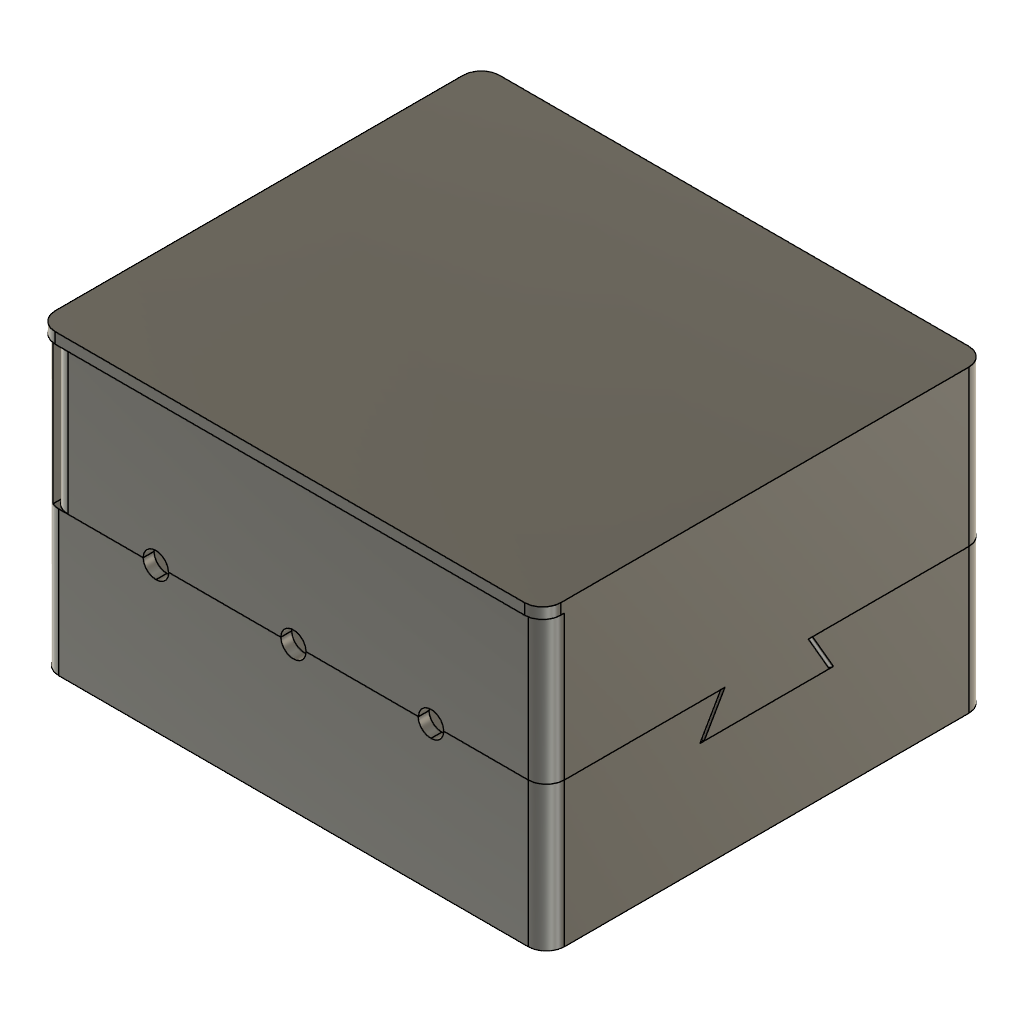
Box (Autodesk Fusion 360 design; units mm, degrees)
part number: 2026-10-24-19-44-33-604
Autodesk Fusion 360 part; units mm, degrees
sketch "Sketch1" plane through (0, 0, 0) normal (0, 0, 1) x (1, 0, 0)
  line L0 (-45, 0) -> (40, 0)
  line L1 (40, 0) -> (40, 122)
  line L2 (-45, 0) -> (-45, 122)
  line L3 (-45, 122) -> (40, 122)
  dimension "d1" = 85
  dimension "d2" = 122
  dimension "d3" = 122
  constraint horizontal L0
  constraint perpendicular L0 L1
  constraint perpendicular L0 L2
  measures "d1" distance of L0.start L0.end
  measures "d2" distance of L0.end L1.end
  measures "d3" distance of L0.start L2.end
extrude "Extrude1" add sketch "Sketch1" along normal blind 10 makes body 1
sketch "Sketch2" plane through (-45, 0, 0) normal (1, 0, 0) x (0, 1, 0)
  line L0 (122, 10) -> (0, 10)
  line L1 (74.4268, 10) -> (74.4268, 21)
  line L2 (74.4268, 21) -> (65.4268, 21)
  line L3 (65.4268, 21) -> (65.4268, 10)
  line L4 (55, 10) -> (41.8, 10)
  line L5 (55, 10) -> (55, 29)
  line L6 (55, 29) -> (41.8, 29)
  line L7 (41.8, 29) -> (41.8, 10)
  line L8 (122, 29) -> (122, 10)
  line L9 (0, 29) -> (0, 10)
  line L10 (122, 29) -> (122, 32)
  line L11 (122, 32) -> (0, 32)
  line L12 (0, 32) -> (0, 29)
  line L13 (122, 0) -> (0, 0)
  line L14 (0, 0) -> (0, 10)
  line L15 (0, 10) -> (122, 10)
  line L16 (122, 10) -> (122, 0)
  dimension "d6" = 11
  dimension "d7" = 9
  dimension "d8" = 13.2
  dimension "d9" = 19
  dimension "d10" = 13.2
  dimension "d11" = 3
  constraint coincident L0 L1.start
  constraint perpendicular L1 L2
  constraint perpendicular L2 L3
  constraint coincident L0 L4.start
  constraint perpendicular L4 L5
  constraint perpendicular L5 L6
  constraint coincident L0.start L8.end
  constraint perpendicular L0 L8
  constraint coincident L0.end L9.end
  constraint perpendicular L0 L9
  constraint perpendicular L10 L11
  measures "d6" distance of L1.start L1.end
  measures "d7" distance of L1.end L2.end
  measures "d8" distance of L4.start L4.end
  measures "d9" distance of L4.start L5.end
  measures "d10" distance of L5.end L6.end
  measures "d11" distance of L8.start L10.end
extrude "Extrude2" add sketch "Sketch2" along normal blind 3 contours L0 L1 L2 L3 L5 L6 L7 L8 L9 L10 L11 L12 L15 bodies 1
sketch "Sketch5" plane through (0, 0, 0) normal (0, 1, 0) x (1, 0, 0)
  line L0 (-35, -16) -> (-45, -16)
  line L1 (-45, -16) -> (40, -16)
  line L2 (40, -16) -> (40, -10)
  line L3 (40, -10) -> (-41.9493, -10)
  line L4 (-41.9493, -10) -> (-45, -10)
  line L5 (-45, -10) -> (-45, -16)
  constraint perpendicular L1 L2
  constraint parallel L3 L4
  constraint perpendicular L1 L5
extrude "Extrude3" add sketch "Sketch5" along normal blind 41.8 bodies 1
extrude "Extrude4" add 1 faces at (40, 13.9333, 8.6667) along direction (1, 0, 0) blind 55 on bodies 1 bodies 1
sketch "Sketch8" plane through (-45, 0, 0) normal (-1, 0, 0) x (0, -1, 0)
  line L0 (-41.8, 10) -> (-55, 10)
  line L1 (-55, 10) -> (-55, 29)
  line L2 (-55, 29) -> (-41.8, 29)
  line L3 (-41.8, 29) -> (-41.8, 10)
  line L4 (0, 0) -> (0, 32)
  line L5 (0, 32) -> (-122, 32)
  line L6 (-122, 32) -> (-122, 0)
  line L7 (-122, 0) -> (0, 0)
  line L8 (-74.4268, 10) -> (-74.4268, 21)
  line L9 (-74.4268, 21) -> (-65.4268, 21)
  line L10 (-65.4268, 21) -> (-65.4268, 10)
  line L11 (-65.4268, 10) -> (-74.4268, 10)
  line L12 (0, 0) -> (0, 80)
  line L13 (0, 0) -> (-122, 0)
  line L14 (-122, 0) -> (-122, 80)
  line L15 (-122, 80) -> (0, 80)
  dimension "d24" = 80
  constraint coincident L4.start L7.end
  constraint perpendicular L7 L12
  constraint coincident L6.end L7.start
  constraint perpendicular L5 L14
  constraint perpendicular L12 L15
  measures "d24" distance of L4.start L12.end
extrude "Extrude5" add sketch "Sketch8" against normal blind 3 contours L5 L12 L14 L15 bodies 1
move_body "Move1" bodies 1 to x (1, 0, 0) y (0, 1, 0) z (0, 0, 1) at (-25, 0, 0)
sketch "Sketch12" plane through (0, 0, 0) normal (0, 1, 0) x (1, 0, 0)
  line L0 (70, 0) -> (70, -40)
  line L1 (70, -40) -> (-70, -40)
  line L2 (-70, -40) -> (-70, 0)
  line L3 (-70, 0) -> (70, 0)
  dimension "d29" = 40
  constraint vertical L0
  constraint perpendicular L0 L1
  constraint perpendicular L1 L2
  constraint perpendicular L0 L3
  measures "d29" distance of L0.start L0.end
extrude "Extrude6" add sketch "Sketch12" along normal blind 41.8 bodies 1
sketch "Sketch13" plane through (0, 0, 0) normal (0, 1, 0) x (1, 0, 0)
  circle A0 centre (0, -40) radius 3.5
  circle A1 centre (-35, -40) radius 3.5
  circle A2 centre (35, -40) radius 3.5
  dimension "d32" = 7
  dimension "d33" = 35
  dimension "d34" = 7
  measures "d32" diameter of A0
  measures "d33" distance of A0.centre A1.centre
  measures "d34" diameter of A1
extrude "Extrude7" cut sketch "Sketch13" along normal blind 45 bodies 1
sketch "Sketch14" plane through (0, 0, 40) normal (0, 0, 1) x (-1, 0, 0)
  line L0 (-31.5, 0) -> (-31.5, -41.8)
  line L1 (-31.5, -41.8) -> (-3.5, -41.8)
  line L2 (-3.5, 0) -> (-31.5, 0)
  line L3 (-3.5, -3) -> (-17.6, -3)
  line L4 (3.5, -3) -> (17.6, -3)
  line L5 (17.6, -3) -> (17.6, -35.2)
  line L6 (-17.6, -35.2) -> (-17.6, -3)
  line L7 (3.5, -3) -> (-3.5, -3)
  line L8 (17.6, -35.2) -> (17.6, -42)
  line L9 (-17.6, -35.2) -> (-17.6, -42)
  line L10 (-17.6, -42) -> (17.6, -42)
  dimension "d39" = 14.1
  dimension "d40" = 14.1
  dimension "d41" = 32.2
  dimension "d42" = 35.2
  constraint horizontal L3
  constraint perpendicular L4 L5
  constraint parallel L3 L7
  constraint parallel L5 L8
  constraint vertical L9
  constraint perpendicular L8 L10
  measures "d39" distance of L3.start L3.end
  measures "d40" distance of L4.start L4.end
  measures "d41" distance of L4.end L5.end
  measures "d42" distance of L5.end L6.start
extrude "Extrude8" cut sketch "Sketch14" against normal blind 8.2 bodies 1
sketch "Sketch15" plane through (0, 0, 0) normal (0, -1, 0) x (1, 0, 0)
  arc A0 (31.5, 40) -> (38.5, 40) centre (35, 40) ccw
  line L0 (31.5, 40) -> (3.5, 40)
  arc A1 (-3.5, 40) -> (3.5, 40) centre (0, 40) ccw
  line L1 (-3.5, 40) -> (-31.5, 40)
  arc A2 (-38.5, 40) -> (-31.5, 40) centre (-35, 40) ccw
  line L2 (-38.5, 40) -> (-67, 40)
  line L3 (-67, 40) -> (-67, 80)
  line L4 (-67, 80) -> (-70, 80)
  line L5 (-70, 80) -> (-70, 0)
  line L6 (-70, 0) -> (70, 0)
  line L7 (70, 0) -> (70, 40)
  line L8 (70, 40) -> (38.5, 40)
  line L9 (-38.5, 40) -> (-31.5, 40)
  line L10 (31.5, 40) -> (38.5, 40)
  constraint coincident A2.start L2.start
  constraint coincident L1.end A2.end
  constraint coincident A0.start L0.start
  constraint coincident A0.end L8.end
extrude "Extrude9" add sketch "Sketch15" against normal blind 41.8 contours A0 L10 | A2 L9 bodies 1
sketch "Sketch16" plane through (0, 0, 0) normal (0, -1, 0) x (1, 0, 0)
sketch "Sketch17" plane through (0, 0, 40) normal (0, 0, 1) x (-1, 0, 0)
  line L0 (17.6, -41.8) -> (67, -41.8)
  line L1 (67, -41.8) -> (67, 0)
  line L2 (67, 0) -> (3.5, 0)
  line L3 (3.5, 0) -> (3.5, -3)
  line L4 (3.5, -3) -> (17.6, -3)
  line L5 (17.6, -3) -> (17.6, -41.8)
  line L6 (3.5, -3) -> (17.6, -3)
  line L7 (17.6, -35.2) -> (17.6, -42)
  line L8 (-31.5, -41.8) -> (-3.5, -41.8)
  line L9 (17.6, -3) -> (17.6, -35.2)
  line L10 (-3.5, 0) -> (-31.5, 0)
  line L11 (-17.6, -42) -> (17.6, -42)
  line L12 (-3.5, -3) -> (-17.6, -3)
  line L13 (-17.6, -35.2) -> (-17.6, -42)
  line L14 (3.5, -3) -> (-3.5, -3)
  line L15 (-17.6, -35.2) -> (-17.6, -3)
  line L16 (41.5, -3) -> (55.6, -3)
  line L17 (55.6, -35.2) -> (55.6, -42)
  line L18 (6.5, -41.8) -> (34.5, -41.8)
  line L19 (55.6, -3) -> (55.6, -35.2)
  line L20 (20.4, -42) -> (55.6, -42)
  line L21 (34.5, -3) -> (20.4, -3)
  line L22 (20.4, -35.2) -> (20.4, -42)
  line L23 (41.5, -3) -> (34.5, -3)
  line L24 (20.4, -35.2) -> (20.4, -3)
  line L25 (-41.5, -3) -> (-34.5, -3)
  line L26 (-34.5, -3) -> (-20.4, -3)
  line L27 (-55.6, -3) -> (-55.6, -35.2)
  line L28 (-41.5, -3) -> (-55.6, -3)
  line L29 (-55.6, -35.2) -> (-55.6, -42)
  line L30 (-20.4, -35.2) -> (-20.4, -42)
  line L31 (-20.4, -35.2) -> (-20.4, -3)
  line L32 (-20.4, -42) -> (-55.6, -42)
  point P0 (-20.6, -38.0704)
  point P1 (-34.5, -41.8)
  dimension "d48" = 14.1
  dimension "d49" = 14.1
  dimension "d50" = 32.2
  dimension "d51" = 35.2
  dimension "d52" = 14.1
  dimension "d53" = 14.1
  dimension "d54" = 32.2
  dimension "d55" = 35.2
  constraint horizontal L12
  constraint perpendicular L6 L9
  constraint parallel L12 L14
  constraint parallel L7 L9
  constraint vertical L13
  constraint perpendicular L7 L11
  constraint horizontal L21
  constraint perpendicular L16 L19
  constraint parallel L21 L23
  constraint parallel L17 L19
  constraint vertical L22
  constraint perpendicular L17 L20
  measures "d48" distance of L12.end L12.start
  measures "d49" distance of L4.end L3.end
  measures "d50" distance of L4.end L7.start
  measures "d51" distance of L13.start L7.start
  measures "d52" distance of L21.end L21.start
  measures "d53" distance of L16.end L16.start
  measures "d54" distance of L16.end L17.start
  measures "d55" distance of L22.start L17.start
extrude "Extrude10" cut sketch "Sketch17" against normal blind 8.2 contours L0 L16 L17 L18 L19 L21 L22 L23 L24 bodies 1
sketch "Sketch21" plane through (0, 0, 0) normal (0, 1, 0) x (1, 0, 0)
  circle A0 centre (-38, -40) radius 3.5
  line L0 (0, -53) -> (0, -49)
  circle A1 centre (38, -40) radius 3.5
  circle A2 centre (0, -40) radius 3.5
  dimension "d59" = 7
  dimension "d64" = 7
  constraint vertical L0
  constraint symmetric A0 L0 A1
  measures "d59" diameter of A0
  measures "d64" diameter of A2
extrude "Extrude11" cut sketch "Sketch21" along normal blind 3 contours A0 | A1 bodies 1
extrude "Extrude12" cut sketch "Sketch17" against normal blind 8.2 contours L25 L26 L27 L28 L29 L30 L31 L32 bodies 1
sketch "Sketch25" plane through (0, 122, 0) normal (0, 1, 0) x (-1, 0, 0)
  line L0 (-70, 0) -> (70, 0)
  line L1 (70, 0) -> (70, 80)
  line L2 (70, 80) -> (67, 80)
  line L3 (67, 80) -> (67, 10)
  line L4 (67, 10) -> (-70, 10)
  line L5 (-70, 10) -> (-70, 0)
  line L6 (-70, 0) -> (-70, 40)
  line L7 (-70, 40) -> (70, 40)
  line L8 (70, 40) -> (70, 0)
  line L9 (-70, 0) -> (70, 0)
  circle A0 centre (0, 20) radius 10
  dimension "d65" = 20
  constraint coincident L0.start L5.end
  constraint perpendicular L4 L6
  constraint midpoint L1 L7.end
  constraint perpendicular L1 L7
  constraint coincident L0.end L1.start
  measures "d65" diameter of A0
extrude "Extrude13" add sketch "Sketch25" against normal blind 3 contours L0 L1 L3 L4 L5 L6 L7 L8 L9 | L3 L4 L6 L7 bodies 1
sketch "Sketch26" plane through (70, 0, 0) normal (1, 0, 0) x (0, 1, 0)
  line L0 (119, 10) -> (41.8, 10)
  line L1 (41.8, 10) -> (41.8, 40)
  line L2 (41.8, 40) -> (0, 40)
  line L3 (0, 40) -> (0, 0)
  line L4 (0, 0) -> (122, 0)
  line L5 (122, 0) -> (122, 40)
  line L6 (122, 40) -> (119, 40)
  line L7 (119, 40) -> (119, 10)
  line L8 (0, 0) -> (122, 0)
  line L9 (122, 40) -> (0, 40)
  line L10 (0, 0) -> (0, 40)
  line L11 (122, 40) -> (122, 0)
  constraint coincident L3.end L4.start
  constraint coincident L4.end L5.start
  constraint coincident L5.end L6.start
  constraint coincident L2.end L3.start
extrude "Extrude14" add sketch "Sketch26" against normal blind 3 bodies 1
sketch "Sketch27" plane through (-70, 0, 0) normal (-1, 0, 0) x (0, -1, 0)
  line L0 (-74.4268, 10) -> (-74.4268, 21)
  line L1 (-74.4268, 21) -> (-65.4268, 21)
  line L2 (-65.4268, 21) -> (-65.4268, 10)
  line L3 (-65.4268, 10) -> (-74.4268, 10)
  line L4 (-41.8, 29) -> (-41.8, 10)
  line L5 (-41.8, 10) -> (-55, 10)
  line L6 (-55, 10) -> (-55, 29)
  line L7 (-55, 29) -> (-41.8, 29)
  line L8 (-122, 80) -> (-122, 0)
  line L9 (-122, 0) -> (0, 0)
  line L10 (0, 0) -> (0, 80)
  line L11 (0, 80) -> (-122, 80)
  line L12 (-43.6795, 70) -> (-61, 100)
  line L13 (-61, 100) -> (-78.3205, 70)
  line L14 (-78.3205, 70) -> (-43.6795, 70)
  point P0 (-61, 80)
  dimension "d70" = 61
  dimension "d71" = 10
  measures "d70" distance of L10.end P0
  measures "d71" distance of P0 L14
extrude "Extrude15" cut sketch "Sketch27" against normal blind 20 contours L11 L12 L13 L14 bodies 1
sketch "Sketch28" plane through (70, 0, 0) normal (1, 0, 0) x (0, 1, 0)
  line L0 (122, 40) -> (0, 40)
  line L1 (0, 40) -> (0, 0)
  line L2 (0, 0) -> (122, 0)
  line L3 (122, 0) -> (122, 40)
  line L4 (78.3205, 30) -> (61, 60)
  line L5 (61, 60) -> (43.6795, 30)
  line L6 (43.6795, 30) -> (78.3205, 30)
  point P0 (61, 40)
  dimension "d74" = 10
  measures "d74" distance of P0 L6
extrude "Extrude16" cut sketch "Sketch28" against normal blind 3 contours L0 L4 L5 L6 bodies 1
sketch "Sketch29" plane through (70, 0, 0) normal (1, 0, 0) x (0, 1, 0)
  line L0 (43.6795, 30) -> (49.453, 40)
  line L1 (49.453, 40) -> (0, 40)
  line L2 (0, 40) -> (0, 0)
  line L3 (0, 0) -> (122, 0)
  line L4 (122, 0) -> (122, 40)
  line L5 (122, 40) -> (72.547, 40)
  line L6 (72.547, 40) -> (78.3205, 30)
  line L7 (78.3205, 30) -> (43.6795, 30)
  line L8 (122, 40) -> (122, 80)
  line L9 (122, 80) -> (0, 80)
  line L10 (0, 80) -> (0, 40)
  line L11 (122, 40) -> (72.547, 40)
  line L12 (72.547, 40) -> (78.3205, 30)
  line L13 (78.3205, 30) -> (43.6795, 30)
  line L14 (49.453, 40) -> (43.6795, 30)
  line L15 (49.453, 40) -> (0, 40)
  constraint coincident L4.end L5.start
  constraint perpendicular L5 L8
  constraint perpendicular L8 L9
  constraint coincident L1.end L2.start
  constraint perpendicular L1 L10
  constraint coincident L5.end L6.start
  constraint coincident L6.end L7.start
  constraint coincident L0.start L7.end
  constraint coincident L0.end L1.start
extrude "Extrude17" add sketch "Sketch29" against normal blind 3 separate body contours L0 L1 L5 L6 L7 L8 L9 L10 L11 L12 L13 L14 L15 makes body 2
sketch "Sketch30" plane through (0, 0, 0) normal (0, -1, 0) x (1, 0, 0)
  line L0 (70, 40) -> (70, 80)
  line L1 (70, 80) -> (67, 80)
  line L2 (67, 80) -> (67, 40)
  line L3 (67, 40) -> (70, 40)
  line L4 (-3.1757, 80) -> (-67, 80)
  line L5 (-67, 80) -> (-67, 40)
  line L6 (-67, 40) -> (70, 40)
  line L7 (70, 80) -> (70, 40)
  line L8 (70, 80) -> (-67, 80)
  constraint horizontal L4
  constraint coincident L0.start L3.end
  constraint perpendicular L0 L6
  constraint coincident L0.end L1.start
  constraint perpendicular L5 L8
  constraint coincident L4.start L8
extrude "Extrude18" add sketch "Sketch30" against normal blind 3 contours L2 L4 L5 L6 L8 bodies 2
sketch "Sketch31" plane through (-70, 0, 0) normal (-1, 0, 0) x (0, -1, 0)
  line L0 (-78.3205, 70) -> (-72.547, 80)
  line L1 (-72.547, 80) -> (-122, 80)
  line L2 (-122, 80) -> (-122, 0)
  line L3 (-122, 0) -> (0, 0)
  line L4 (0, 0) -> (0, 80)
  line L5 (0, 80) -> (-49.453, 80)
  line L6 (-49.453, 80) -> (-43.6795, 70)
  line L7 (-43.6795, 70) -> (-78.3205, 70)
  line L8 (-74.4268, 10) -> (-74.4268, 21)
  line L9 (-74.4268, 21) -> (-65.4268, 21)
  line L10 (-65.4268, 21) -> (-65.4268, 10)
  line L11 (-65.4268, 10) -> (-74.4268, 10)
  line L12 (-41.8, 29) -> (-41.8, 10)
  line L13 (-41.8, 10) -> (-55, 10)
  line L14 (-55, 10) -> (-55, 29)
  line L15 (-55, 29) -> (-41.8, 29)
  line L16 (0, 80) -> (-49.453, 80)
  line L17 (-43.6795, 70) -> (-49.453, 80)
  line L18 (-43.6795, 70) -> (-78.3205, 70)
  line L19 (-72.547, 80) -> (-78.3205, 70)
  line L20 (-72.547, 80) -> (-120, 80)
  line L21 (-120, 80) -> (-122, 80)
  line L22 (-122, 80) -> (-122, 83)
  line L23 (-122, 83) -> (0, 83)
  line L24 (0, 83) -> (0, 80)
  dimension "d83" = 3
  constraint coincident L4.end L5.start
  constraint coincident L5.end L6.start
  constraint coincident L6.end L7.start
  constraint coincident L0.start L7.end
  constraint coincident L0.end L1.start
  constraint coincident L1 L20.end
  constraint coincident L1.end L2.start
  constraint perpendicular L1 L22
  constraint perpendicular L22 L23
  constraint perpendicular L5 L24
  measures "d83" distance of L1.end L22.end
extrude "Extrude19" add sketch "Sketch31" against normal blind 3 separate body contours L0 L1 L5 L6 L7 L16 L17 L18 L19 L20 L21 L22 L23 L24 makes body 3
sketch "Sketch32" plane through (0, 122, 0) normal (0, 1, 0) x (-1, 0, 0)
  line L0 (-70, 80) -> (-70, 40)
  line L1 (-70, 40) -> (-67, 40)
  line L2 (-67, 40) -> (-67, 80)
  line L3 (-67, 80) -> (-70, 80)
  line L4 (70, 80) -> (-70, 80)
  line L5 (-70, 80) -> (-70, 83)
  line L6 (-70, 83) -> (70, 83)
  line L7 (70, 83) -> (70, 80)
  dimension "d86" = 3
  constraint coincident L0.start L3.end
  constraint perpendicular L0 L4
  constraint perpendicular L3 L5
  constraint perpendicular L5 L6
  constraint perpendicular L4 L7
  measures "d86" distance of L0.start L5.end
extrude "Extrude20" add sketch "Sketch32" against normal blind 123 contours L3 L4 L5 L6 L7 bodies 2 3
sketch "Sketch33" plane through (0, 0, 0) normal (0, -1, 0) x (1, 0, 0)
  line L0 (70, 40) -> (70, 80)
  line L1 (70, 80) -> (-67, 80)
  line L2 (-67, 80) -> (-67, 40)
  line L3 (-67, 40) -> (70, 40)
  circle A0 centre (0, 40) radius 3.5
  circle A1 centre (-38.108, 40) radius 3.5
  circle A2 centre (38.108, 40) radius 3.5
  dimension "d89" = 7
  dimension "d90" = 38.108
  dimension "d91" = 7
  constraint coincident L3 A0.centre
  measures "d89" diameter of A0
  measures "d90" distance of A0.centre A1.centre
  measures "d91" diameter of A1
extrude "Extrude21" cut sketch "Sketch33" against normal blind 3 contours L3 A2 | L3 A2 | L3 A0 | L3 A0 | L3 A1 | L3 A1 bodies 1 2
sketch "Sketch34" plane through (0, 122, 0) normal (0, 1, 0) x (-1, 0, 0)
  line L0 (-70, 83) -> (-70, 40)
  line L1 (-70, 40) -> (-67, 40)
  line L2 (-67, 40) -> (-67, 80)
  line L3 (-67, 80) -> (70, 80)
  line L4 (70, 80) -> (70, 83)
  line L5 (70, 83) -> (-70, 83)
  line L6 (-70, 83) -> (70, 83)
  line L7 (70, 40) -> (-70, 40)
  line L8 (-70, 83) -> (-70, 40)
  line L9 (70, 83) -> (70, 40)
  line L10 (70, 83) -> (67, 83)
  line L11 (67, 83) -> (67, 40)
  line L12 (70, 40) -> (67, 40)
  line L13 (70, 83) -> (70, 40)
  dimension "d96" = 3
  constraint coincident L0.start L5.end
  constraint coincident L4.end L5.start
  constraint coincident L0.end L1.start
  constraint perpendicular L0 L7
  constraint perpendicular L7 L9
  constraint perpendicular L4 L10
  constraint coincident L7 L11.end
  constraint perpendicular L7 L11
  measures "d96" distance of L4.end L10.end
extrude "Extrude22" add sketch "Sketch34" against normal blind 3 contours L2 L3 L7 L11 | L3 L7 L9 L11 L12 L13 bodies 2
extrude "Extrude23" cut sketch "Sketch34" against normal blind 3 contours L3 L7 L9 L11 L12 L13 bodies 1
fillet "Fillet1" radius 5 1 edges at (-70, 122, 61.5) on bodies 2
fillet "Fillet2" radius 5 1 edges at (-70, 122, 20) on bodies 1
fillet "Fillet3" radius 5 1 edges at (70, 122, 61.5) on bodies 2
fillet "Fillet4" radius 5 1 edges at (70, 122, 20) on bodies 1
fillet "Fillet5" radius 5 2 edges at (70, 0, 20) (70, 0, 60) on bodies 1 2
fillet "Fillet6" radius 5 1 edges at (-70, 0, 40) on bodies 1
fillet "Fillet7" radius 5 1 edges at (-67, 0, 60) on bodies 2
fillet "Fillet8" radius 5 1 edges at (-70, -1, 81.5) on bodies 2
fillet "Fillet9" radius 5 1 edges at (70, -1, 81.5) on bodies 2
fillet "Fillet10" radius 1 1 edges at (-70, 75.4338, 75) on bodies 1
fillet "Fillet11" radius 1 1 edges at (-70, 46.5662, 75) on bodies 1
fillet "Fillet12" radius 1 2 edges at (-67, 46.5662, 75) (-67, 75.4338, 75) on bodies 1
fillet "Fillet13" radius 1 4 edges at (70, 46.5662, 35) (67, 46.5662, 35) (67, 75.4338, 35) (70, 75.4338, 35) on bodies 1
